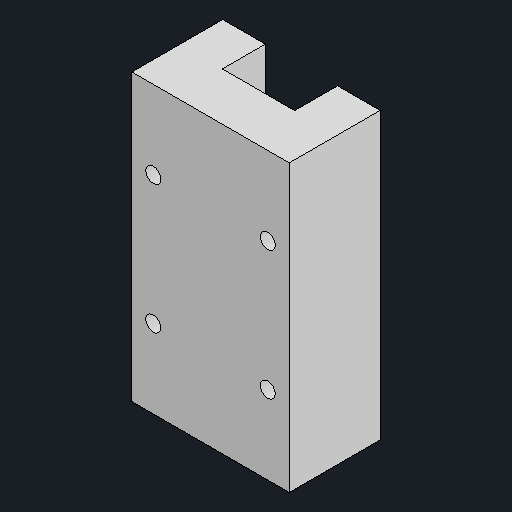
# Autodesk Inventor part: SBI20SL
Saved by Autodesk Inventor 2027.1 (Build 311270010, 270A)
## iProperties
Created: 2026-11-14
Part Number: SBI20SL
Material: Generic
Description: SBC catalogue mounting envelope 44 x 79.8 maximum listed length; raceway section simplified
Document SubType Name: Modeling
Designer: queezz
Density: 1 g/cm^3
Appearance: Default
Author: queezz
Autodesk Inventor part; units mm, degrees
ref_plane "Carriage body plane" through (0, 0, 4.6) normal (0, 0, 1) x (1, 0, 0)
sketch "Carriage body" plane through (0, 0, 4.6) normal (0, 0, 1) x (1, 0, 0)
  line L0 (-22, -39.9) -> (22, -39.9)
  line L1 (22, -39.9) -> (22, 39.9)
  line L2 (22, 39.9) -> (-22, 39.9)
  line L3 (-22, 39.9) -> (-22, -39.9)
  constraints: 8 end point, 2 parallel, 1 horizontal, 1 perpendicular
extrude "Block envelope" add sketch "Carriage body" along normal blind 25.4
ref_plane "Rail channel plane" through (0, 0, 16.6) normal (0, 0, 1) x (1, 0, 0)
sketch "Rail channel" plane through (0, 0, 16.6) normal (0, 0, 1) x (1, 0, 0)
  line L0 (-10.1, -41) -> (10.1, -41)
  line L1 (10.1, -41) -> (10.1, 41)
  line L2 (10.1, 41) -> (-10.1, 41)
  line L3 (-10.1, 41) -> (-10.1, -41)
  constraints: 8 end point, 2 parallel, 1 horizontal, 1 perpendicular
extrude "Rail clearance" cut sketch "Rail channel" against normal blind 12.1
ref_plane "M5 thread envelopes layout plane" through (0, 0, 30) normal (0, 0, 1) x (1, 0, 0)
sketch "M5 thread envelopes layout" plane through (0, 0, 30) normal (0, 0, 1) x (1, 0, 0)
  circle A0 centre (-16, -18) radius 2.1
  circle A1 centre (-16, 18) radius 2.1
  circle A2 centre (16, -18) radius 2.1
  circle A3 centre (16, 18) radius 2.1
  constraints: 4 centre point
extrude "M5 thread envelopes" cut sketch "M5 thread envelopes layout" against normal blind 5
body "Solid1"
